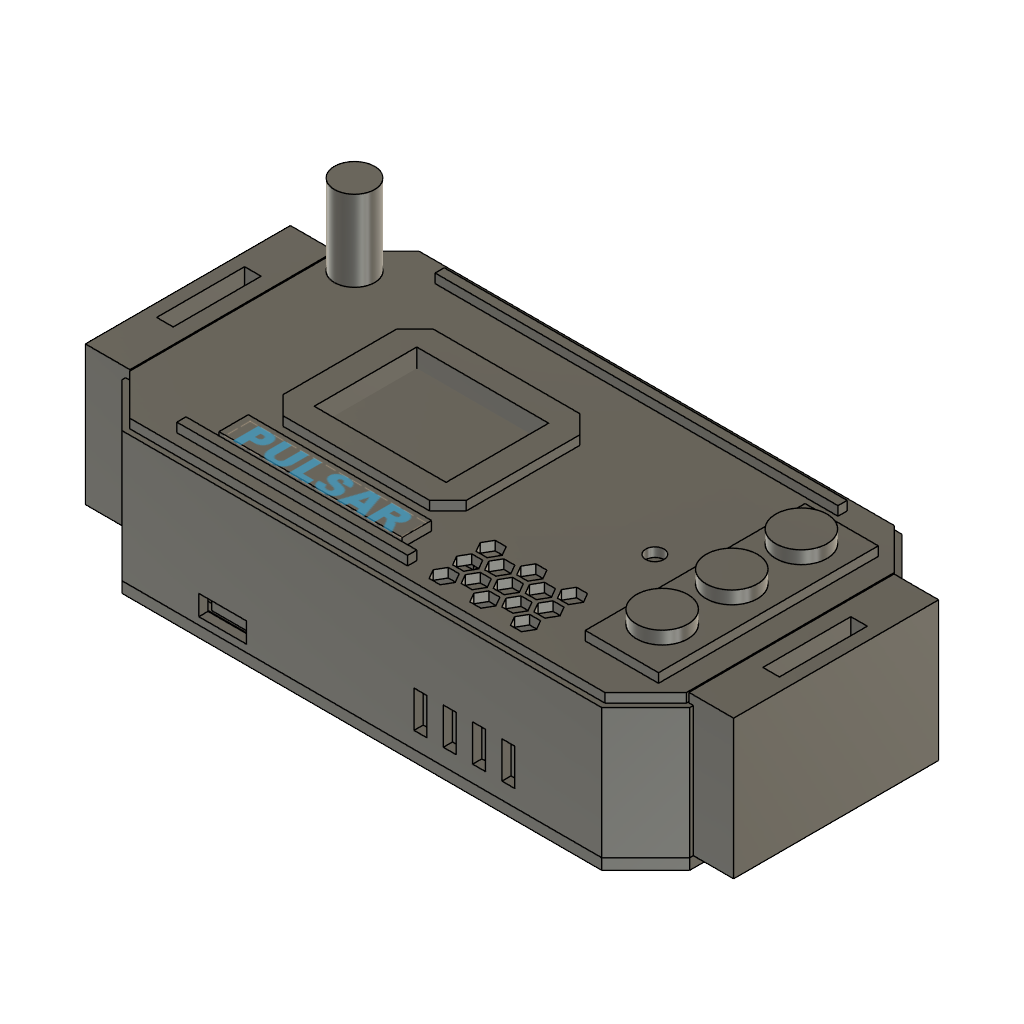
PULSAR02 (Autodesk Fusion 360 design; units mm, degrees)
part number: 2026-11-15-19-57-41-079
Autodesk Fusion 360 part; units mm, degrees
sketch "Housing_outer_profile" plane through (0, 0, 0) normal (0, 0, 1) x (1, 0, 0)
  line L0 (-65.5, -41) -> (65.5, -41)
  line L1 (65.5, -41) -> (77.5, -29)
  line L2 (77.5, -29) -> (77.5, 29)
  line L3 (77.5, 29) -> (65.5, 41)
  line L4 (65.5, 41) -> (-65.5, 41)
  line L5 (-65.5, 41) -> (-77.5, 29)
  line L6 (-77.5, 29) -> (-77.5, -29)
  line L7 (-77.5, -29) -> (-65.5, -41)
extrude "Housing_outer_solid" add sketch "Housing_outer_profile" along normal blind 35.5 makes body 1
ref_plane "WorkPlane1" through (0, 0, 35.5) normal (0, 0, 1) x (1, 0, 0)
sketch "Roof_plateau_profile" plane through (0, 0, 35.5) normal (0, 0, 1) x (1, 0, 0)
  line L0 (-64.8787, -39.5) -> (64.8787, -39.5)
  line L1 (64.8787, -39.5) -> (76, -28.3787)
  line L2 (76, -28.3787) -> (76, 28.3787)
  line L3 (76, 28.3787) -> (64.8787, 39.5)
  line L4 (64.8787, 39.5) -> (-64.8787, 39.5)
  line L5 (-64.8787, 39.5) -> (-76, 28.3787)
  line L6 (-76, 28.3787) -> (-76, -28.3787)
  line L7 (-76, -28.3787) -> (-64.8787, -39.5)
extrude "Roof_plateau" add sketch "Roof_plateau_profile" along normal blind 2.5 bodies 1
ref_plane "WorkPlane2" through (0, 0, -0.1) normal (0, 0, 1) x (1, 0, 0)
sketch "Housing_cavity_profile" plane through (0, 0, -0.1) normal (0, 0, 1) x (1, 0, 0)
  line L0 (-64.4645, -38.5) -> (64.4645, -38.5)
  line L1 (64.4645, -38.5) -> (75, -27.9645)
  line L2 (75, -27.9645) -> (75, 27.9645)
  line L3 (75, 27.9645) -> (64.4645, 38.5)
  line L4 (64.4645, 38.5) -> (-64.4645, 38.5)
  line L5 (-64.4645, 38.5) -> (-75, 27.9645)
  line L6 (-75, 27.9645) -> (-75, -27.9645)
  line L7 (-75, -27.9645) -> (-64.4645, -38.5)
extrude "Housing_cavity" cut sketch "Housing_cavity_profile" along normal blind 35.6 bodies 1
ref_plane "WorkPlane3" through (0, 0, 2.3) normal (0, 0, 1) x (1, 0, 0)
sketch "Boss_profiles" plane through (0, 0, 2.3) normal (0, 0, 1) x (1, 0, 0)
  circle A0 centre (-60, -34.5) radius 4.25
  circle A1 centre (-60, 34.5) radius 4.25
  circle A2 centre (52, -34.5) radius 4.25
  circle A3 centre (52, 34.5) radius 4.25
extrude "Internal_screw_bosses" add sketch "Boss_profiles" along normal blind 34.2 bodies 1
ref_plane "WorkPlane4" through (0, 0, 2.3) normal (0, 0, 1) x (1, 0, 0)
sketch "Boss_pilot_profiles" plane through (0, 0, 2.3) normal (0, 0, 1) x (1, 0, 0)
  circle A0 centre (-60, -34.5) radius 0.85
  circle A1 centre (-60, 34.5) radius 0.85
  circle A2 centre (52, -34.5) radius 0.85
  circle A3 centre (52, 34.5) radius 0.85
extrude "Boss_pilot_holes" cut sketch "Boss_pilot_profiles" along normal blind 9 bodies 1
ref_plane "WorkPlane5" through (0, 0, 25.5) normal (0, 0, 1) x (1, 0, 0)
sketch "Antenna_socket_profile" plane through (0, 0, 25.5) normal (0, 0, 1) x (1, 0, 0)
  circle A0 centre (-69, 26) radius 5
extrude "Antenna_socket" add sketch "Antenna_socket_profile" along normal blind 11 bodies 1
sketch "Strap_loop_profiles" plane through (0, 0, 0) normal (0, 0, 1) x (1, 0, 0)
  line L0 (-88.5, -28) -> (-76.3, -28)
  line L1 (-76.3, -28) -> (-76.3, 28)
  line L2 (-76.3, 28) -> (-88.5, 28)
  line L3 (-88.5, 28) -> (-88.5, -28)
  line L4 (-85, -12) -> (-80.5, -12)
  line L5 (-80.5, -12) -> (-80.5, 12)
  line L6 (-80.5, 12) -> (-85, 12)
  line L7 (-85, 12) -> (-85, -12)
  line L8 (76.3, -28) -> (88.5, -28)
  line L9 (88.5, -28) -> (88.5, 28)
  line L10 (88.5, 28) -> (76.3, 28)
  line L11 (76.3, 28) -> (76.3, -28)
  line L12 (80.5, -12) -> (85, -12)
  line L13 (85, -12) -> (85, 12)
  line L14 (85, 12) -> (80.5, 12)
  line L15 (80.5, 12) -> (80.5, -12)
extrude "Strap_loops" add sketch "Strap_loop_profiles" along normal blind 38 bodies 1
ref_plane "WorkPlane6" through (0, 0, 29.5) normal (0, 0, 1) x (1, 0, 0)
sketch "Display_seat_profile" plane through (0, 0, 29.5) normal (0, 0, 1) x (1, 0, 0)
  line L0 (-53.5, 18) -> (9.5, 18)
  line L1 (9.5, 18) -> (9.5, 20)
  line L2 (9.5, 20) -> (-53.5, 20)
  line L3 (-53.5, 20) -> (-53.5, 18)
  line L4 (-53.5, -20) -> (9.5, -20)
  line L5 (9.5, -20) -> (9.5, -18)
  line L6 (9.5, -18) -> (-53.5, -18)
  line L7 (-53.5, -18) -> (-53.5, -20)
  line L8 (-53.5, -18) -> (-51.5, -18)
  line L9 (-51.5, -18) -> (-51.5, 18)
  line L10 (-51.5, 18) -> (-53.5, 18)
  line L11 (-53.5, 18) -> (-53.5, -18)
  line L12 (7.5, -18) -> (9.5, -18)
  line L13 (9.5, -18) -> (9.5, 18)
  line L14 (9.5, 18) -> (7.5, 18)
  line L15 (7.5, 18) -> (7.5, -18)
extrude "Display_seat" add sketch "Display_seat_profile" along normal blind 7 bodies 1
ref_plane "WorkPlane7" through (0, 0, 26.5) normal (0, 0, 1) x (1, 0, 0)
sketch "Switch_pocket_profiles" plane through (0, 0, 26.5) normal (0, 0, 1) x (1, 0, 0)
  line L0 (52.2, -12.7) -> (67.8, -12.7)
  line L1 (67.8, -12.7) -> (67.8, -11.2)
  line L2 (67.8, -11.2) -> (52.2, -11.2)
  line L3 (52.2, -11.2) -> (52.2, -12.7)
  line L4 (52.2, -26.8) -> (67.8, -26.8)
  line L5 (67.8, -26.8) -> (67.8, -25.3)
  line L6 (67.8, -25.3) -> (52.2, -25.3)
  line L7 (52.2, -25.3) -> (52.2, -26.8)
  line L8 (52.2, -25.3) -> (53.7, -25.3)
  line L9 (53.7, -25.3) -> (53.7, -12.7)
  line L10 (53.7, -12.7) -> (52.2, -12.7)
  line L11 (52.2, -12.7) -> (52.2, -25.3)
  line L12 (66.3, -25.3) -> (67.8, -25.3)
  line L13 (67.8, -25.3) -> (67.8, -12.7)
  line L14 (67.8, -12.7) -> (66.3, -12.7)
  line L15 (66.3, -12.7) -> (66.3, -25.3)
  line L16 (52.2, 6.3) -> (67.8, 6.3)
  line L17 (67.8, 6.3) -> (67.8, 7.8)
  line L18 (67.8, 7.8) -> (52.2, 7.8)
  line L19 (52.2, 7.8) -> (52.2, 6.3)
  line L20 (52.2, -7.8) -> (67.8, -7.8)
  line L21 (67.8, -7.8) -> (67.8, -6.3)
  line L22 (67.8, -6.3) -> (52.2, -6.3)
  line L23 (52.2, -6.3) -> (52.2, -7.8)
  line L24 (52.2, -6.3) -> (53.7, -6.3)
  line L25 (53.7, -6.3) -> (53.7, 6.3)
  line L26 (53.7, 6.3) -> (52.2, 6.3)
  line L27 (52.2, 6.3) -> (52.2, -6.3)
  line L28 (66.3, -6.3) -> (67.8, -6.3)
  line L29 (67.8, -6.3) -> (67.8, 6.3)
  line L30 (67.8, 6.3) -> (66.3, 6.3)
  line L31 (66.3, 6.3) -> (66.3, -6.3)
  line L32 (52.2, 25.3) -> (67.8, 25.3)
  line L33 (67.8, 25.3) -> (67.8, 26.8)
  line L34 (67.8, 26.8) -> (52.2, 26.8)
  line L35 (52.2, 26.8) -> (52.2, 25.3)
  line L36 (52.2, 11.2) -> (67.8, 11.2)
  line L37 (67.8, 11.2) -> (67.8, 12.7)
  line L38 (67.8, 12.7) -> (52.2, 12.7)
  line L39 (52.2, 12.7) -> (52.2, 11.2)
  line L40 (52.2, 12.7) -> (53.7, 12.7)
  line L41 (53.7, 12.7) -> (53.7, 25.3)
  line L42 (53.7, 25.3) -> (52.2, 25.3)
  line L43 (52.2, 25.3) -> (52.2, 12.7)
  line L44 (66.3, 12.7) -> (67.8, 12.7)
  line L45 (67.8, 12.7) -> (67.8, 25.3)
  line L46 (67.8, 25.3) -> (66.3, 25.3)
  line L47 (66.3, 25.3) -> (66.3, 12.7)
extrude "Switch_pockets" add sketch "Switch_pocket_profiles" along normal blind 10 bodies 1
ref_plane "WorkPlane8" through (0, 0, 38) normal (0, 0, 1) x (1, 0, 0)
sketch "Raised_bezel_profile" plane through (0, 0, 38) normal (0, 0, 1) x (1, 0, 0)
  line L0 (-42, -20.5) -> (-2, -20.5)
  line L1 (-2, -20.5) -> (3, -15.5)
  line L2 (3, -15.5) -> (3, 15.5)
  line L3 (3, 15.5) -> (-2, 20.5)
  line L4 (-2, 20.5) -> (-42, 20.5)
  line L5 (-42, 20.5) -> (-47, 15.5)
  line L6 (-47, 15.5) -> (-47, -15.5)
  line L7 (-47, -15.5) -> (-42, -20.5)
  line L8 (-40, -14) -> (-4, -14)
  line L9 (-4, -14) -> (-4, 14)
  line L10 (-4, 14) -> (-40, 14)
  line L11 (-40, 14) -> (-40, -14)
extrude "Raised_bezel" add sketch "Raised_bezel_profile" along normal blind 2.5 bodies 1
ref_plane "WorkPlane9" through (0, 0, 38) normal (0, 0, 1) x (1, 0, 0)
sketch "Raised_plates_profile" plane through (0, 0, 38) normal (0, 0, 1) x (1, 0, 0)
  line L0 (50, -30) -> (70, -30)
  line L1 (70, -30) -> (70, 30)
  line L2 (70, 30) -> (50, 30)
  line L3 (50, 30) -> (50, -30)
  line L4 (-47, -33) -> (3, -33)
  line L5 (3, -33) -> (3, -25)
  line L6 (3, -25) -> (-47, -25)
  line L7 (-47, -25) -> (-47, -33)
  line L8 (-55, 34) -> (55, 34)
  line L9 (55, 34) -> (55, 36.5)
  line L10 (55, 36.5) -> (-55, 36.5)
  line L11 (-55, 36.5) -> (-55, 34)
  line L12 (-55, -36.5) -> (8, -36.5)
  line L13 (8, -36.5) -> (8, -34)
  line L14 (8, -34) -> (-55, -34)
  line L15 (-55, -34) -> (-55, -36.5)
extrude "Raised_plates_and_rails" add sketch "Raised_plates_profile" along normal blind 2.5 bodies 1
ref_plane "WorkPlane10" through (0, 0, 33.5) normal (0, 0, 1) x (1, 0, 0)
sketch "Roof_cut_profiles" plane through (0, 0, 33.5) normal (0, 0, 1) x (1, 0, 0)
  line L0 (-40, -14) -> (-4, -14)
  line L1 (-4, -14) -> (-4, 14)
  line L2 (-4, 14) -> (-40, 14)
  line L3 (-40, 14) -> (-40, -14)
  circle A0 centre (60, -19) radius 4.8
  circle A1 centre (60, 0) radius 4.8
  circle A2 centre (60, 19) radius 4.8
  line L4 (18.4, -33.9086) -> (16.9, -31.3105)
  line L5 (16.9, -31.3105) -> (13.9, -31.3105)
  line L6 (13.9, -31.3105) -> (12.4, -33.9086)
  line L7 (12.4, -33.9086) -> (13.9, -36.5067)
  line L8 (13.9, -36.5067) -> (16.9, -36.5067)
  line L9 (16.9, -36.5067) -> (18.4, -33.9086)
  line L10 (18.4, -27.5) -> (16.9, -24.9019)
  line L11 (16.9, -24.9019) -> (13.9, -24.9019)
  line L12 (13.9, -24.9019) -> (12.4, -27.5)
  line L13 (12.4, -27.5) -> (13.9, -30.0981)
  line L14 (13.9, -30.0981) -> (16.9, -30.0981)
  line L15 (16.9, -30.0981) -> (18.4, -27.5)
  line L16 (18.4, -21.0914) -> (16.9, -18.4933)
  line L17 (16.9, -18.4933) -> (13.9, -18.4933)
  line L18 (13.9, -18.4933) -> (12.4, -21.0914)
  line L19 (12.4, -21.0914) -> (13.9, -23.6895)
  line L20 (13.9, -23.6895) -> (16.9, -23.6895)
  line L21 (16.9, -23.6895) -> (18.4, -21.0914)
  line L22 (23.95, -30.7043) -> (22.45, -28.1062)
  line L23 (22.45, -28.1062) -> (19.45, -28.1062)
  line L24 (19.45, -28.1062) -> (17.95, -30.7043)
  line L25 (17.95, -30.7043) -> (19.45, -33.3024)
  line L26 (19.45, -33.3024) -> (22.45, -33.3024)
  line L27 (22.45, -33.3024) -> (23.95, -30.7043)
  line L28 (23.95, -24.2957) -> (22.45, -21.6976)
  line L29 (22.45, -21.6976) -> (19.45, -21.6976)
  line L30 (19.45, -21.6976) -> (17.95, -24.2957)
  line L31 (17.95, -24.2957) -> (19.45, -26.8938)
  line L32 (19.45, -26.8938) -> (22.45, -26.8938)
  line L33 (22.45, -26.8938) -> (23.95, -24.2957)
  line L34 (29.5, -33.9086) -> (28, -31.3105)
  line L35 (28, -31.3105) -> (25, -31.3105)
  line L36 (25, -31.3105) -> (23.5, -33.9086)
  line L37 (23.5, -33.9086) -> (25, -36.5067)
  line L38 (25, -36.5067) -> (28, -36.5067)
  line L39 (28, -36.5067) -> (29.5, -33.9086)
  line L40 (29.5, -27.5) -> (28, -24.9019)
  line L41 (28, -24.9019) -> (25, -24.9019)
  line L42 (25, -24.9019) -> (23.5, -27.5)
  line L43 (23.5, -27.5) -> (25, -30.0981)
  line L44 (25, -30.0981) -> (28, -30.0981)
  line L45 (28, -30.0981) -> (29.5, -27.5)
  line L46 (29.5, -21.0914) -> (28, -18.4933)
  line L47 (28, -18.4933) -> (25, -18.4933)
  line L48 (25, -18.4933) -> (23.5, -21.0914)
  line L49 (23.5, -21.0914) -> (25, -23.6895)
  line L50 (25, -23.6895) -> (28, -23.6895)
  line L51 (28, -23.6895) -> (29.5, -21.0914)
  line L52 (35.05, -30.7043) -> (33.55, -28.1062)
  line L53 (33.55, -28.1062) -> (30.55, -28.1062)
  line L54 (30.55, -28.1062) -> (29.05, -30.7043)
  line L55 (29.05, -30.7043) -> (30.55, -33.3024)
  line L56 (30.55, -33.3024) -> (33.55, -33.3024)
  line L57 (33.55, -33.3024) -> (35.05, -30.7043)
  line L58 (35.05, -24.2957) -> (33.55, -21.6976)
  line L59 (33.55, -21.6976) -> (30.55, -21.6976)
  line L60 (30.55, -21.6976) -> (29.05, -24.2957)
  line L61 (29.05, -24.2957) -> (30.55, -26.8938)
  line L62 (30.55, -26.8938) -> (33.55, -26.8938)
  line L63 (33.55, -26.8938) -> (35.05, -24.2957)
  line L64 (40.6, -33.9086) -> (39.1, -31.3105)
  line L65 (39.1, -31.3105) -> (36.1, -31.3105)
  line L66 (36.1, -31.3105) -> (34.6, -33.9086)
  line L67 (34.6, -33.9086) -> (36.1, -36.5067)
  line L68 (36.1, -36.5067) -> (39.1, -36.5067)
  line L69 (39.1, -36.5067) -> (40.6, -33.9086)
  line L70 (40.6, -27.5) -> (39.1, -24.9019)
  line L71 (39.1, -24.9019) -> (36.1, -24.9019)
  line L72 (36.1, -24.9019) -> (34.6, -27.5)
  line L73 (34.6, -27.5) -> (36.1, -30.0981)
  line L74 (36.1, -30.0981) -> (39.1, -30.0981)
  line L75 (39.1, -30.0981) -> (40.6, -27.5)
  line L76 (40.6, -21.0914) -> (39.1, -18.4933)
  line L77 (39.1, -18.4933) -> (36.1, -18.4933)
  line L78 (36.1, -18.4933) -> (34.6, -21.0914)
  line L79 (34.6, -21.0914) -> (36.1, -23.6895)
  line L80 (36.1, -23.6895) -> (39.1, -23.6895)
  line L81 (39.1, -23.6895) -> (40.6, -21.0914)
  circle A3 centre (39, 0) radius 2.5
extrude "Roof_cuts" cut sketch "Roof_cut_profiles" along normal blind 10 bodies 1
ref_plane "WorkPlane11" through (0, 0, 27) normal (0, 0, 1) x (1, 0, 0)
sketch "Antenna_hole_profile" plane through (0, 0, 27) normal (0, 0, 1) x (1, 0, 0)
  circle A0 centre (-69, 26) radius 2.8
extrude "Antenna_hole" cut sketch "Antenna_hole_profile" along normal blind 16 bodies 1
ref_plane "WorkPlane12" through (0, 0, 2) normal (0, 0, 1) x (1, 0, 0)
sketch "USB_charger_profile" plane through (0, 0, 2) normal (0, 0, 1) x (1, 0, 0)
  line L0 (74, -5.25) -> (78.5, -5.25)
  line L1 (78.5, -5.25) -> (78.5, 5.25)
  line L2 (78.5, 5.25) -> (74, 5.25)
  line L3 (74, 5.25) -> (74, -5.25)
extrude "USB_charger_opening" cut sketch "USB_charger_profile" along normal blind 7 bodies 1
ref_plane "WorkPlane13" through (0, 0, 11.5) normal (0, 0, 1) x (1, 0, 0)
sketch "USB_esp32_profile" plane through (0, 0, 11.5) normal (0, 0, 1) x (1, 0, 0)
  line L0 (-78.5, -5) -> (-74, -5)
  line L1 (-74, -5) -> (-74, 5)
  line L2 (-74, 5) -> (-78.5, 5)
  line L3 (-78.5, 5) -> (-78.5, -5)
extrude "USB_esp32_opening" cut sketch "USB_esp32_profile" along normal blind 7.5 bodies 1
ref_plane "WorkPlane14" through (0, 0, 2) normal (0, 0, 1) x (1, 0, 0)
sketch "microSD_slot_profile" plane through (0, 0, 2) normal (0, 0, 1) x (1, 0, 0)
  line L0 (-44.5, -42) -> (-31.5, -42)
  line L1 (-31.5, -42) -> (-31.5, -37.5)
  line L2 (-31.5, -37.5) -> (-44.5, -37.5)
  line L3 (-44.5, -37.5) -> (-44.5, -42)
extrude "microSD_slot" cut sketch "microSD_slot_profile" along normal blind 5.5 bodies 1
ref_plane "WorkPlane15" through (0, 0, 4.5) normal (0, 0, 1) x (1, 0, 0)
sketch "Inlet_slot_profiles" plane through (0, 0, 4.5) normal (0, 0, 1) x (1, 0, 0)
  line L0 (14.25, -42) -> (17.75, -42)
  line L1 (17.75, -42) -> (17.75, -37.5)
  line L2 (17.75, -37.5) -> (14.25, -37.5)
  line L3 (14.25, -37.5) -> (14.25, -42)
  line L4 (22.25, -42) -> (25.75, -42)
  line L5 (25.75, -42) -> (25.75, -37.5)
  line L6 (25.75, -37.5) -> (22.25, -37.5)
  line L7 (22.25, -37.5) -> (22.25, -42)
  line L8 (30.25, -42) -> (33.75, -42)
  line L9 (33.75, -42) -> (33.75, -37.5)
  line L10 (33.75, -37.5) -> (30.25, -37.5)
  line L11 (30.25, -37.5) -> (30.25, -42)
  line L12 (38.25, -42) -> (41.75, -42)
  line L13 (41.75, -42) -> (41.75, -37.5)
  line L14 (41.75, -37.5) -> (38.25, -37.5)
  line L15 (38.25, -37.5) -> (38.25, -42)
extrude "Air_inlet_slots" cut sketch "Inlet_slot_profiles" along normal blind 10 bodies 1
ref_plane "WorkPlane16" through (0, 0, 39.7) normal (0, 0, 1) x (1, 0, 0)
sketch "Logo_profile" plane through (0, 0, 39.7) normal (0, 0, 1) x (1, 0, 0)
  line L0 (-46, -32.5) -> (2, -32.5) construction
  line L1 (2, -32.5) -> (2, -25.5) construction
  line L2 (2, -25.5) -> (-46, -25.5) construction
  line L3 (-46, -25.5) -> (-46, -32.5) construction
  dimension "d67" = 7
ref_plane "WorkPlane17" through (0, 0, -3) normal (0, 0, 1) x (1, 0, 0)
sketch "Cover_plate_profile" plane through (0, 0, -3) normal (0, 0, 1) x (1, 0, 0)
  line L0 (-65.5, -41) -> (65.5, -41)
  line L1 (65.5, -41) -> (77.5, -29)
  line L2 (77.5, -29) -> (77.5, 29)
  line L3 (77.5, 29) -> (65.5, 41)
  line L4 (65.5, 41) -> (-65.5, 41)
  line L5 (-65.5, 41) -> (-77.5, 29)
  line L6 (-77.5, 29) -> (-77.5, -29)
  line L7 (-77.5, -29) -> (-65.5, -41)
extrude "Bottom_cover_plate" add sketch "Cover_plate_profile" along normal blind 3 separate body makes body 2
sketch "Cover_rim_profile" plane through (0, 0, 0) normal (0, 0, 1) x (1, 0, 0)
  line L0 (-64.2988, -38.1) -> (64.2988, -38.1)
  line L1 (64.2988, -38.1) -> (74.6, -27.7988)
  line L2 (74.6, -27.7988) -> (74.6, 27.7988)
  line L3 (74.6, 27.7988) -> (64.2988, 38.1)
  line L4 (64.2988, 38.1) -> (-64.2988, 38.1)
  line L5 (-64.2988, 38.1) -> (-74.6, 27.7988)
  line L6 (-74.6, 27.7988) -> (-74.6, -27.7988)
  line L7 (-74.6, -27.7988) -> (-64.2988, -38.1)
  line L8 (-63.3875, -35.9) -> (63.3875, -35.9)
  line L9 (63.3875, -35.9) -> (72.4, -26.8875)
  line L10 (72.4, -26.8875) -> (72.4, 26.8875)
  line L11 (72.4, 26.8875) -> (63.3875, 35.9)
  line L12 (63.3875, 35.9) -> (-63.3875, 35.9)
  line L13 (-63.3875, 35.9) -> (-72.4, 26.8875)
  line L14 (-72.4, 26.8875) -> (-72.4, -26.8875)
  line L15 (-72.4, -26.8875) -> (-63.3875, -35.9)
extrude "Cover_locating_rim" add sketch "Cover_rim_profile" along normal blind 1.8 bodies 2
sketch "Cover_rim_notch_profiles" plane through (0, 0, 0) normal (0, 0, 1) x (1, 0, 0)
  circle A0 centre (-60, -34.5) radius 4.75
  circle A1 centre (-60, 34.5) radius 4.75
  circle A2 centre (52, -34.5) radius 4.75
  circle A3 centre (52, 34.5) radius 4.75
extrude "Cover_rim_notches" cut sketch "Cover_rim_notch_profiles" along normal blind 2.8 bodies 2
sketch "Deck_post_profiles" plane through (0, 0, 0) normal (0, 0, 1) x (1, 0, 0)
  circle A0 centre (-63, -22) radius 3
  circle A1 centre (66, -22) radius 3
  circle A2 centre (-12, 29) radius 3
  circle A3 centre (32, 29) radius 3
  circle A4 centre (-12, -29) radius 3
extrude "Deck_posts" add sketch "Deck_post_profiles" along normal blind 9.5 bodies 2
ref_plane "WorkPlane18" through (0, 0, 4.5) normal (0, 0, 1) x (1, 0, 0)
sketch "Deck_post_pilot_profiles" plane through (0, 0, 4.5) normal (0, 0, 1) x (1, 0, 0)
  circle A0 centre (-63, -22) radius 0.85
  circle A1 centre (66, -22) radius 0.85
  circle A2 centre (-12, 29) radius 0.85
  circle A3 centre (32, 29) radius 0.85
  circle A4 centre (-12, -29) radius 0.85
extrude "Deck_post_pilots" cut sketch "Deck_post_pilot_profiles" along normal blind 6 bodies 2
ref_plane "WorkPlane19" through (0, 0, -3) normal (0, 0, 1) x (1, 0, 0)
sketch "Cover_cut_profiles" plane through (0, 0, -3) normal (0, 0, 1) x (1, 0, 0)
  line L0 (-15, -5) -> (-1, -5)
  line L1 (-1, -5) -> (-1, 5)
  line L2 (-1, 5) -> (-15, 5)
  line L3 (-15, 5) -> (-15, -5)
  circle A0 centre (15, 0) radius 5
  circle A1 centre (-60, -34.5) radius 1.2
  circle A2 centre (-60, 34.5) radius 1.2
  circle A3 centre (52, -34.5) radius 1.2
  circle A4 centre (52, 34.5) radius 1.2
extrude "Cover_windows_and_screw_holes" cut sketch "Cover_cut_profiles" along normal blind 6 bodies 2
ref_plane "WorkPlane20" through (0, 0, -3) normal (0, 0, 1) x (1, 0, 0)
sketch "Cover_cbore_profiles" plane through (0, 0, -3) normal (0, 0, 1) x (1, 0, 0)
  circle A0 centre (-60, -34.5) radius 2.1
  circle A1 centre (-60, 34.5) radius 2.1
  circle A2 centre (52, -34.5) radius 2.1
  circle A3 centre (52, 34.5) radius 2.1
extrude "Cover_counterbores" cut sketch "Cover_cbore_profiles" along normal blind 1.5 bodies 2
ref_plane "WorkPlane21" through (0, 0, 9.5) normal (0, 0, 1) x (1, 0, 0)
sketch "Deck_profile" plane through (0, 0, 9.5) normal (0, 0, 1) x (1, 0, 0)
  line L0 (-64.0503, -37.5) -> (64.0503, -37.5)
  line L1 (64.0503, -37.5) -> (74, -27.5503)
  line L2 (74, -27.5503) -> (74, 27.5503)
  line L3 (74, 27.5503) -> (64.0503, 37.5)
  line L4 (64.0503, 37.5) -> (-64.0503, 37.5)
  line L5 (-64.0503, 37.5) -> (-74, 27.5503)
  line L6 (-74, 27.5503) -> (-74, -27.5503)
  line L7 (-74, -27.5503) -> (-64.0503, -37.5)
extrude "Deck_plate" add sketch "Deck_profile" along normal blind 2 separate body makes body 3
ref_plane "WorkPlane22" through (0, 0, 8.5) normal (0, 0, 1) x (1, 0, 0)
sketch "Deck_cut_profiles" plane through (0, 0, 8.5) normal (0, 0, 1) x (1, 0, 0)
  line L0 (8.5, -39.5) -> (44.5, -39.5)
  line L1 (44.5, -39.5) -> (44.5, -16.5)
  line L2 (44.5, -16.5) -> (8.5, -16.5)
  line L3 (8.5, -16.5) -> (8.5, -39.5)
  line L4 (-23, -13) -> (-19, -13)
  line L5 (-19, -13) -> (-19, 13)
  line L6 (-19, 13) -> (-23, 13)
  line L7 (-23, 13) -> (-23, -13)
  line L8 (34, 10) -> (44, 10)
  line L9 (44, 10) -> (44, 15)
  line L10 (44, 15) -> (34, 15)
  line L11 (34, 15) -> (34, 10)
  circle A0 centre (-60, -34.5) radius 5.45
  circle A1 centre (-60, 34.5) radius 5.45
  circle A2 centre (52, -34.5) radius 5.45
  circle A3 centre (52, 34.5) radius 5.45
  circle A4 centre (-63, -22) radius 1.1
  circle A5 centre (66, -22) radius 1.1
  circle A6 centre (-12, 29) radius 1.1
  circle A7 centre (32, 29) radius 1.1
  circle A8 centre (-12, -29) radius 1.1
extrude "Deck_cuts" cut sketch "Deck_cut_profiles" along normal blind 5 bodies 3
ref_plane "WorkPlane23" through (0, 0, 10.5) normal (0, 0, 1) x (1, 0, 0)
sketch "Deck_cbore_profiles" plane through (0, 0, 10.5) normal (0, 0, 1) x (1, 0, 0)
  circle A0 centre (-63, -22) radius 2.1
  circle A1 centre (66, -22) radius 2.1
  circle A2 centre (-12, 29) radius 2.1
  circle A3 centre (32, 29) radius 2.1
  circle A4 centre (-12, -29) radius 2.1
extrude "Deck_counterbores" cut sketch "Deck_cbore_profiles" along normal blind 2 bodies 3
ref_plane "WorkPlane24" through (0, 0, 27) normal (0, 0, 1) x (1, 0, 0)
sketch "Antenna_peg_profile" plane through (0, 0, 27) normal (0, 0, 1) x (1, 0, 0)
  circle A0 centre (-69, 26) radius 2.5
extrude "Antenna_peg" add sketch "Antenna_peg_profile" along normal blind 11 separate body makes body 4
ref_plane "WorkPlane25" through (0, 0, 38) normal (0, 0, 1) x (1, 0, 0)
sketch "Antenna_head_profile" plane through (0, 0, 38) normal (0, 0, 1) x (1, 0, 0)
  circle A0 centre (-69, 26) radius 5.5
extrude "Antenna_head" add sketch "Antenna_head_profile" along normal blind 22 bodies 4
ref_plane "WorkPlane26" through (0, 0, 33.7) normal (0, 0, 1) x (1, 0, 0)
sketch "Cap1_flange_profile" plane through (0, 0, 33.7) normal (0, 0, 1) x (1, 0, 0)
  circle A0 centre (60, -19) radius 5.75
extrude "Cap1_flange" add sketch "Cap1_flange_profile" along normal blind 1 separate body makes body 5
ref_plane "WorkPlane27" through (0, 0, 34.7) normal (0, 0, 1) x (1, 0, 0)
sketch "Cap1_stem_profile" plane through (0, 0, 34.7) normal (0, 0, 1) x (1, 0, 0)
  circle A0 centre (60, -19) radius 4.5
extrude "Cap1_stem" add sketch "Cap1_stem_profile" along normal blind 7.3 bodies 5
ref_plane "WorkPlane28" through (0, 0, 41.5) normal (0, 0, 1) x (1, 0, 0)
sketch "Cap1_head_profile" plane through (0, 0, 41.5) normal (0, 0, 1) x (1, 0, 0)
  circle A0 centre (60, -19) radius 7
extrude "Cap1_head" add sketch "Cap1_head_profile" along normal blind 3.5 bodies 5
ref_plane "WorkPlane29" through (0, 0, 33.7) normal (0, 0, 1) x (1, 0, 0)
sketch "Cap2_flange_profile" plane through (0, 0, 33.7) normal (0, 0, 1) x (1, 0, 0)
  circle A0 centre (60, 0) radius 5.75
extrude "Cap2_flange" add sketch "Cap2_flange_profile" along normal blind 1 separate body makes body 6
ref_plane "WorkPlane30" through (0, 0, 34.7) normal (0, 0, 1) x (1, 0, 0)
sketch "Cap2_stem_profile" plane through (0, 0, 34.7) normal (0, 0, 1) x (1, 0, 0)
  circle A0 centre (60, 0) radius 4.5
extrude "Cap2_stem" add sketch "Cap2_stem_profile" along normal blind 7.3 bodies 6
ref_plane "WorkPlane31" through (0, 0, 41.5) normal (0, 0, 1) x (1, 0, 0)
sketch "Cap2_head_profile" plane through (0, 0, 41.5) normal (0, 0, 1) x (1, 0, 0)
  circle A0 centre (60, 0) radius 7
extrude "Cap2_head" add sketch "Cap2_head_profile" along normal blind 3.5 bodies 6
ref_plane "WorkPlane32" through (0, 0, 33.7) normal (0, 0, 1) x (1, 0, 0)
sketch "Cap3_flange_profile" plane through (0, 0, 33.7) normal (0, 0, 1) x (1, 0, 0)
  circle A0 centre (60, 19) radius 5.75
extrude "Cap3_flange" add sketch "Cap3_flange_profile" along normal blind 1 separate body makes body 7
ref_plane "WorkPlane33" through (0, 0, 34.7) normal (0, 0, 1) x (1, 0, 0)
sketch "Cap3_stem_profile" plane through (0, 0, 34.7) normal (0, 0, 1) x (1, 0, 0)
  circle A0 centre (60, 19) radius 4.5
extrude "Cap3_stem" add sketch "Cap3_stem_profile" along normal blind 7.3 bodies 7
ref_plane "WorkPlane34" through (0, 0, 41.5) normal (0, 0, 1) x (1, 0, 0)
sketch "Cap3_head_profile" plane through (0, 0, 41.5) normal (0, 0, 1) x (1, 0, 0)
  circle A0 centre (60, 19) radius 7
extrude "Cap3_head" add sketch "Cap3_head_profile" along normal blind 3.5 bodies 7
ref_plane "WorkPlane35" through (0, 0, 0.5) normal (0, 0, 1) x (1, 0, 0)
sketch "MAX30102_2.5x1.5_profile" plane through (0, 0, 0.5) normal (0, 0, 1) x (1, 0, 0)
  line L0 (-20.5, -7.5) -> (4.5, -7.5)
  line L1 (4.5, -7.5) -> (4.5, 7.5)
  line L2 (4.5, 7.5) -> (-20.5, 7.5)
  line L3 (-20.5, 7.5) -> (-20.5, -7.5)
extrude "MAX30102_2.5x1.5" add sketch "MAX30102_2.5x1.5_profile" along normal blind 3.5 separate body makes body 8
ref_plane "WorkPlane36" through (0, 0, 0.5) normal (0, 0, 1) x (1, 0, 0)
sketch "KY039_1.5x1.2_assumed_profile" plane through (0, 0, 0.5) normal (0, 0, 1) x (1, 0, 0)
  line L0 (7.5, -6) -> (22.5, -6)
  line L1 (22.5, -6) -> (22.5, 6)
  line L2 (22.5, 6) -> (7.5, 6)
  line L3 (7.5, 6) -> (7.5, -6)
extrude "KY039_1.5x1.2_assumed" add sketch "KY039_1.5x1.2_assumed_profile" along normal blind 4 separate body makes body 9
ref_plane "WorkPlane37" through (0, 0, 2.2) normal (0, 0, 1) x (1, 0, 0)
sketch "HW373_charger_3x2_profile" plane through (0, 0, 2.2) normal (0, 0, 1) x (1, 0, 0)
  line L0 (44.5, -10) -> (74.5, -10)
  line L1 (74.5, -10) -> (74.5, 10)
  line L2 (74.5, 10) -> (44.5, 10)
  line L3 (44.5, 10) -> (44.5, -10)
extrude "HW373_charger_3x2" add sketch "HW373_charger_3x2_profile" along normal blind 5 separate body makes body 10
ref_plane "WorkPlane38" through (0, 0, 2.2) normal (0, 0, 1) x (1, 0, 0)
sketch "HW668_boost_2.5x1.5_profile" plane through (0, 0, 2.2) normal (0, 0, 1) x (1, 0, 0)
  line L0 (45, 14) -> (70, 14)
  line L1 (70, 14) -> (70, 29)
  line L2 (70, 29) -> (45, 29)
  line L3 (45, 29) -> (45, 14)
extrude "HW668_boost_2.5x1.5" add sketch "HW668_boost_2.5x1.5_profile" along normal blind 6 separate body makes body 11
ref_plane "WorkPlane39" through (0, 0, 2.2) normal (0, 0, 1) x (1, 0, 0)
sketch "MQ135_3.3x2_profile" plane through (0, 0, 2.2) normal (0, 0, 1) x (1, 0, 0)
  line L0 (10, -37.5) -> (43, -37.5)
  line L1 (43, -37.5) -> (43, -17.5)
  line L2 (43, -17.5) -> (10, -17.5)
  line L3 (10, -17.5) -> (10, -37.5)
extrude "MQ135_3.3x2" add sketch "MQ135_3.3x2_profile" along normal blind 16 separate body makes body 12
ref_plane "WorkPlane40" through (0, 0, 2.2) normal (0, 0, 1) x (1, 0, 0)
sketch "MPU6500_2.3x1.5_profile" plane through (0, 0, 2.2) normal (0, 0, 1) x (1, 0, 0)
  line L0 (-50, 19) -> (-27, 19)
  line L1 (-27, 19) -> (-27, 34)
  line L2 (-27, 34) -> (-50, 34)
  line L3 (-50, 34) -> (-50, 19)
extrude "MPU6500_2.3x1.5" add sketch "MPU6500_2.3x1.5_profile" along normal blind 4 separate body makes body 13
ref_plane "WorkPlane41" through (0, 0, 2.2) normal (0, 0, 1) x (1, 0, 0)
sketch "HX711_2x1.5_profile" plane through (0, 0, 2.2) normal (0, 0, 1) x (1, 0, 0)
  line L0 (-72, 9) -> (-52, 9)
  line L1 (-52, 9) -> (-52, 24)
  line L2 (-52, 24) -> (-72, 24)
  line L3 (-72, 24) -> (-72, 9)
extrude "HX711_2x1.5" add sketch "HX711_2x1.5_profile" along normal blind 4.5 separate body makes body 14
ref_plane "WorkPlane42" through (0, 0, 2.2) normal (0, 0, 1) x (1, 0, 0)
sketch "microSD_2.5x1.2_profile" plane through (0, 0, 2.2) normal (0, 0, 1) x (1, 0, 0)
  line L0 (-44, -38) -> (-32, -38)
  line L1 (-32, -38) -> (-32, -13)
  line L2 (-32, -13) -> (-44, -13)
  line L3 (-44, -13) -> (-44, -38)
extrude "microSD_2.5x1.2" add sketch "microSD_2.5x1.2_profile" along normal blind 5 separate body makes body 15
ref_plane "WorkPlane43" through (0, 0, 11.5) normal (0, 0, 1) x (1, 0, 0)
sketch "ESP32_5x3_profile" plane through (0, 0, 11.5) normal (0, 0, 1) x (1, 0, 0)
  line L0 (-73, -15) -> (-23, -15)
  line L1 (-23, -15) -> (-23, 15)
  line L2 (-23, 15) -> (-73, 15)
  line L3 (-73, 15) -> (-73, -15)
extrude "ESP32_5x3" add sketch "ESP32_5x3_profile" along normal blind 11.5 separate body makes body 16
ref_plane "WorkPlane44" through (0, 0, 11.5) normal (0, 0, 1) x (1, 0, 0)
sketch "Battery_5x3x0.8_assumed_profile" plane through (0, 0, 11.5) normal (0, 0, 1) x (1, 0, 0)
  line L0 (-19, -15) -> (31, -15)
  line L1 (31, -15) -> (31, 15)
  line L2 (31, 15) -> (-19, 15)
  line L3 (-19, 15) -> (-19, -15)
extrude "Battery_5x3x0.8_assumed" add sketch "Battery_5x3x0.8_assumed_profile" along normal blind 8 separate body makes body 17
ref_plane "WorkPlane45" through (0, 0, 11.5) normal (0, 0, 1) x (1, 0, 0)
sketch "BMP280_1x1.5_profile" plane through (0, 0, 11.5) normal (0, 0, 1) x (1, 0, 0)
  line L0 (34, -7.5) -> (44, -7.5)
  line L1 (44, -7.5) -> (44, 7.5)
  line L2 (44, 7.5) -> (34, 7.5)
  line L3 (34, 7.5) -> (34, -7.5)
extrude "BMP280_1x1.5" add sketch "BMP280_1x1.5_profile" along normal blind 3.5 separate body makes body 18
ref_plane "WorkPlane46" through (0, 0, 29.5) normal (0, 0, 1) x (1, 0, 0)
sketch "TFT_ST7735_pcb_5.8x3.5_profile" plane through (0, 0, 29.5) normal (0, 0, 1) x (1, 0, 0)
  line L0 (-51, -17.5) -> (7, -17.5)
  line L1 (7, -17.5) -> (7, 17.5)
  line L2 (7, 17.5) -> (-51, 17.5)
  line L3 (-51, 17.5) -> (-51, -17.5)
extrude "TFT_ST7735_pcb_5.8x3.5" add sketch "TFT_ST7735_pcb_5.8x3.5_profile" along normal blind 6 separate body makes body 19
ref_plane "WorkPlane47" through (0, 0, 26.5) normal (0, 0, 1) x (1, 0, 0)
sketch "Switch12x12_1_profile" plane through (0, 0, 26.5) normal (0, 0, 1) x (1, 0, 0)
  line L0 (54, -25) -> (66, -25)
  line L1 (66, -25) -> (66, -13)
  line L2 (66, -13) -> (54, -13)
  line L3 (54, -13) -> (54, -25)
extrude "Switch12x12_1" add sketch "Switch12x12_1_profile" along normal blind 7.5 separate body makes body 20
ref_plane "WorkPlane48" through (0, 0, 26.5) normal (0, 0, 1) x (1, 0, 0)
sketch "Switch12x12_2_profile" plane through (0, 0, 26.5) normal (0, 0, 1) x (1, 0, 0)
  line L0 (54, -6) -> (66, -6)
  line L1 (66, -6) -> (66, 6)
  line L2 (66, 6) -> (54, 6)
  line L3 (54, 6) -> (54, -6)
extrude "Switch12x12_2" add sketch "Switch12x12_2_profile" along normal blind 7.5 separate body makes body 21
ref_plane "WorkPlane49" through (0, 0, 26.5) normal (0, 0, 1) x (1, 0, 0)
sketch "Switch12x12_3_profile" plane through (0, 0, 26.5) normal (0, 0, 1) x (1, 0, 0)
  line L0 (54, 13) -> (66, 13)
  line L1 (66, 13) -> (66, 25)
  line L2 (66, 25) -> (54, 25)
  line L3 (54, 25) -> (54, 13)
extrude "Switch12x12_3" add sketch "Switch12x12_3_profile" along normal blind 7.5 separate body makes body 22
equation "d68 = 'PULSAR'"
named bodies: "PULSAR_Housing", "PULSAR_BottomCover", "PULSAR_Deck", "PULSAR_Antenna", "PULSAR_Cap1", "PULSAR_Cap2", "PULSAR_Cap3", "MAX30102_2.5x1.5", "KY039_1.5x1.2_assumed", "HW373_charger_3x2", "HW668_boost_2.5x1.5", "MQ135_3.3x2", "MPU6500_2.3x1.5", "HX711_2x1.5", "microSD_2.5x1.2", "ESP32_5x3", "Battery_5x3x0.8_assumed", "BMP280_1x1.5", "TFT_ST7735_pcb_5.8x3.5", "Switch12x12_1", "Switch12x12_2", "Switch12x12_3"
